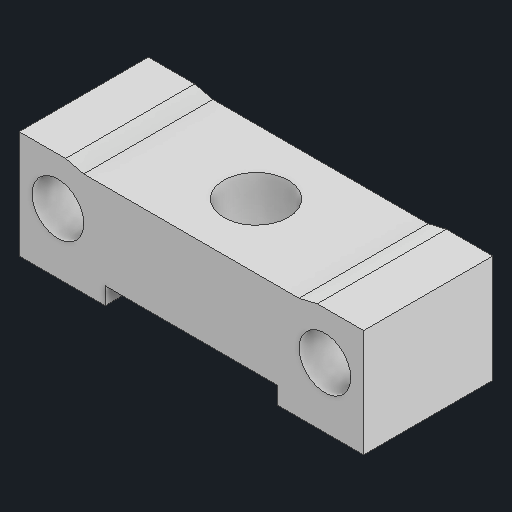
# Autodesk Inventor part: 扭力模块结构
Saved by Autodesk Inventor 2025 (Build 290162000, 162)
## iProperties
Created: 2025-08-27
Part Number: 扭力模块结构
Material: 常规
Document SubType Name: Modeling
Designer: HZD
Density: 1 g/cm^3
Appearance: 默认
Author: HZD
Autodesk Inventor part; units mm, degrees
ref_plane "YZ Plane" through (0, 0, 0) normal (1, 0, 0) x (0, 1, 0)
ref_plane "XZ Plane" through (0, 0, 0) normal (0, 1, 0) x (-1, 0, 0)
ref_plane "XY Plane" through (0, 0, 0) normal (0, 0, 1) x (1, 0, 0)
sketch "草图1" plane through (0, 0, 0) normal (0, 0, 1) x (1, 0, 0)
  line L0 (4, -1.5) -> (-4, -1.5)
  line L1 (-4, -1.5) -> (-4, 1)
  line L2 (-4, 1) -> (4, 1)
  line L3 (4, 1) -> (4, -1.5)
  circle A0 centre (3.1, -0.1) radius 0.6
  line L4 (0, -1.5) -> (0, 1)
  circle A1 centre (-3.1, -0.1) radius 0.6
  point P0 (0, 0)
  dimension "d0" = 8
  dimension "d4" = 1.2
  dimension "d13" = 0.9
  dimension "d18" = 1.1
  dimension "d19" = 2.5
  constraints: 10 end point, 2 centre point, 2 midpoint, 2 parallel, 1 horizontal, 1 perpendicular, 1 symmetric about line, 1 other
  measures "d0" distance of L1.end L2.end
  measures "d4" diameter of A0
  measures "d13" distance from line of A0.centre L3
  measures "d18" distance from line of L2 A1.centre
  measures "d19" distance between parallel lines of L0 L2
extrude "拉伸1" add sketch "草图1" along normal blind 3
sketch "草图2" plane through (0, 0, 0) normal (0, 0, -1) x (-1, 0, 0)
  line L0 (2.5, 0.9) -> (-2.5, 0.9)
  line L1 (-2.5, 0.9) -> (-2.5, 1)
  line L2 (-2.5, 1) -> (2.5, 1)
  line L3 (2.5, 1) -> (2.5, 0.9)
  line L4 (2.5, 0.9) -> (-2.5, 1) construction
  line L5 (-2.5, 0.9) -> (2.5, 1) construction
  line L6 (4, -1.5) -> (-4, -1.5) projected
  line L7 (-4, 1) -> (4, 1) projected
  line L8 (-2.5, 0.9) -> (-2.9228, 1)
  line L9 (0, 1) -> (0, -1.5)
  line L10 (2.5, 0.9) -> (2.9228, 1)
  line L11 (0.5, 0.9) -> (-2, 0.9) projected
  point P0 (0, 0)
  point P1 (0, 0.95)
  dimension "d6" = 5
  constraints: 18 end point, 4 midpoint, 2 collinear, 2 parallel, 1 horizontal, 1 perpendicular, 1 point on line, 1 symmetric about line
  measures "d6" distance of L1.end L2.end
extrude "拉伸2" cut sketch "草图2" against normal blind 3
sketch "草图3" plane through (-2.5, 0.9, 0) normal (0, 1, 0) x (1, 0, 0)
  circle A0 centre (2.5, -1.5) radius 0.75
  line L0 (-1.5, 0) -> (-1.5, -3) projected
  line L1 (-1.5, -1.5) -> (4.3472, -1.5)
  point P0 (2.5, 0)
  dimension "d9" = 1.5
  constraints: 2 end point, 1 centre point, 1 horizontal, 1 midpoint, 1 point on line
  measures "d9" diameter of A0
extrude "拉伸3" cut sketch "草图3" against normal blind 2
sketch "草图4" plane through (-4, -1.5, 0) normal (0, -1, 0) x (1, 0, 0)
  point P0 (4, 0)
sketch "草图5" plane through (0, 0, 3) normal (0, 0, 1) x (1, 0, 0)
  line L0 (2, -1.9) -> (-2, -1.9)
  line L1 (-2, -1.9) -> (-2, -1.1)
  line L2 (-2, -1.1) -> (2, -1.1)
  line L3 (2, -1.1) -> (2, -1.9)
  line L4 (-4, -1.5) -> (4, -1.5) projected
  line L5 (2, -1.9) -> (-2, -1.1) construction
  line L6 (-2, -1.9) -> (2, -1.1) construction
  point P0 (0, 0)
  point P1 (0, -1.5)
  dimension "d14" = 4
  dimension "d15" = 0.4
  constraints: 12 end point, 3 midpoint, 2 parallel, 1 horizontal, 1 perpendicular
  measures "d14" distance of L0.start L0.end
  measures "d15" distance between parallel lines of L2 L4
extrude "拉伸4" cut sketch "草图5" against normal blind 4
